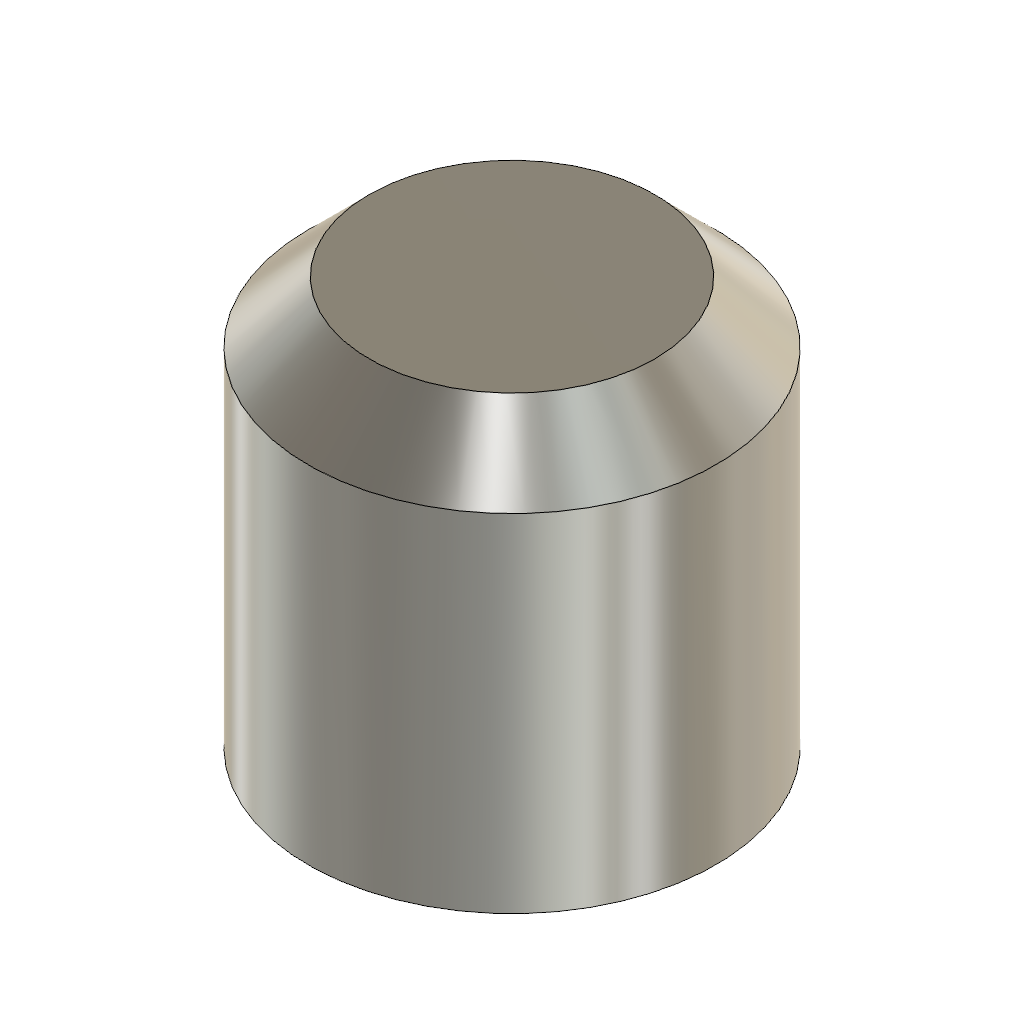
vendor_BevelDiscRim (Autodesk Fusion 360 design; units mm, degrees)
Autodesk Fusion 360 part; units mm, degrees
sketch "Disc sketch" plane through (0, 0, 0) normal (0, 0, 1) x (1, 0, 0)
  circle A0 centre (0, 0) radius 10
extrude "Disc extrude" add sketch "Disc sketch" along normal blind 20
chamfer "Rim bevel" distance 3 angle 45 1 edges at (-9.3233, -3.6162, 20) tangent chain off
equation "height = 20.0 mm"
